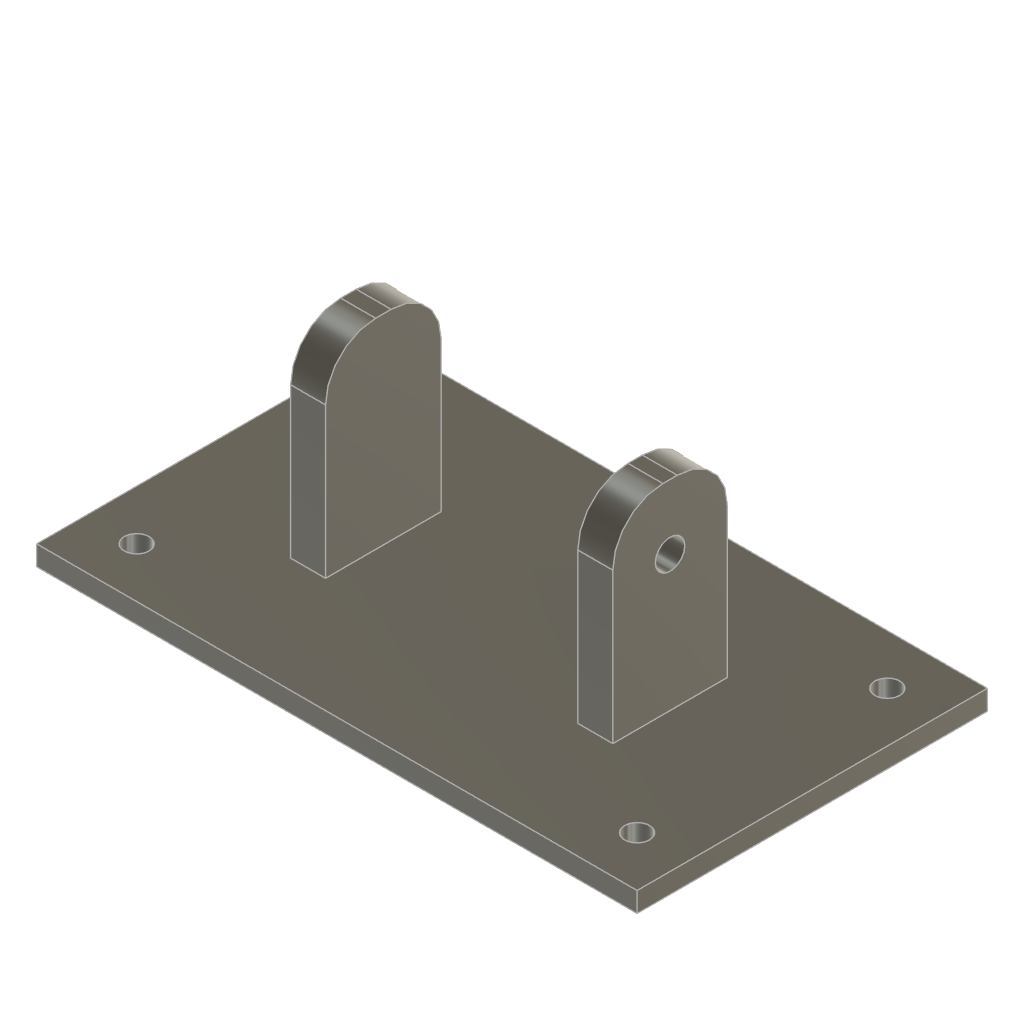
Base (Autodesk Fusion 360 design; units mm, degrees)
part number: 2026-07-20-18-13-44-573
Autodesk Fusion 360 part; units mm, degrees
sketch "Sketch1" plane through (0, 0, 0) normal (0, 0, 1) x (1, 0, 0)
  line L0 (100, -100) -> (-100, -100)
  line L1 (-100, -100) -> (-100, 100)
  line L2 (-100, 100) -> (100, 100)
  line L3 (100, 100) -> (100, -100)
  line L4 (100, -100) -> (-100, 100) construction
  line L5 (-100, -100) -> (100, 100) construction
  dimension "d1" = 200
  dimension "d2" = 200
  constraint horizontal L0
  constraint perpendicular L0 L1
  constraint parallel L0 L2
  constraint parallel L1 L3
  constraint coincident L4 origin
  constraint coincident L5 origin
  measures "d1" distance of L1.end L2.end
  measures "d2" distance of L0.end L1.end
extrude "Extrude1" add sketch "Sketch1" along normal blind 7
sketch "Sketch2" plane through (0, 0, 7) normal (0, 0, 1) x (-1, 0, 0)
  line L0 (-100, -100) -> (100, -100)
  line L1 (100, -100) -> (100, 100)
  line L2 (100, 100) -> (-100, 100)
  line L3 (-100, 100) -> (-100, -100)
  line L4 (0, 0) -> (25.15, 0)
  line L5 (0, 0) -> (-25.15, 0)
  line L6 (25.15, 0) -> (25.15, -10.5)
  line L7 (-25.15, 0) -> (-25.15, -10.5)
  line L8 (-25.15, -10.5) -> (-25.15, 10)
  line L9 (25.15, -10.5) -> (25.15, 11)
  line L10 (25.15, 11) -> (32.15, 11)
  line L11 (32.15, 11) -> (32.15, -10)
  line L12 (32.15, -10) -> (25.15, -10)
  line L13 (25.15, -10) -> (25.15, 11)
  line L14 (-25.15, 10) -> (-32.15, 10)
  line L15 (-32.15, 10) -> (-32.15, -11.3765)
  line L16 (-32.15, -11.3765) -> (-25.15, -11.3765)
  line L17 (-25.15, -11.3765) -> (-25.15, 10)
  dimension "d5" = 25.15
  dimension "d6" = 25.15
  dimension "d7" = 10.5
  dimension "d8" = 10.5
  dimension "d9" = 21.5
  dimension "d10" = 7
  dimension "d11" = 7
  constraint coincident L4.start L5.start
  constraint perpendicular L1 L4
  constraint parallel L4 L5
  constraint perpendicular L4 L6
  constraint perpendicular L5 L7
  constraint perpendicular L5 L8
  constraint perpendicular L4 L9
  constraint horizontal L10
  constraint vertical L11
  constraint horizontal L12
  constraint vertical L13
  constraint horizontal L14
  constraint vertical L15
  constraint horizontal L16
  constraint vertical L17
  measures "d5" distance of L4.start L4.end
  measures "d6" distance of L4.start L5.end
  measures "d7" distance of L4.end L6.end
  measures "d8" distance of L5.end L7.end
  measures "d9" distance of L6.end L9.end
  measures "d10" distance of L9.end L10.end
  measures "d11" distance of L8.end L14.end
extrude "Extrude2" add sketch "Sketch2" along normal blind 30 contours L6 L9 L10 L11 L12 L13 | L7 L8 L14 L15 L16 L17
extrude "Extrude3" add 1 faces at (29.8167, 11.3765, 17) along direction (0, 1, 0) blind 1
extrude "Extrude4" add 1 faces at (-29.8167, 10, 17) along direction (0, 1, 0) blind 1
extrude "Extrude5" add 1 faces at (-27.4833, -11, 17) along direction (0, -1, 0) blind 1
extrude "Extrude6" add 1 faces at (27.4833, -10, 17) along direction (0, -1, 0) blind 1
sketch "Sketch3" plane through (32.15, 0, 0) normal (1, 0, 0) x (0, 1, 0)
  line L0 (-11, 7) -> (12.3765, 7)
  line L1 (12.3765, 7) -> (12.3765, 37)
  line L2 (12.3765, 37) -> (-11, 37)
  line L3 (-11, 37) -> (-11, 7)
  line L4 (0.6883, 37) -> (0.6883, 7)
  line L5 (0.6883, 7) -> (0.6883, 34)
  circle A0 centre (0.7147, 31.0501) radius 2.95
  dimension "d22" = 27
  dimension "d23" = 5.9
  constraint midpoint L2 L4.start
  constraint midpoint L0 L4.end
  constraint perpendicular L0 L5
  constraint coincident L5.end A0
  measures "d22" distance of L4.end L5.end
  measures "d23" diameter of A0
hole "Hole1" at (32.15, 0.7147, 31.0501) direction (-1, 0, 0) diameter 5.9 depth 8 tip angle 180
extrude "Extrude7" add 1 faces at (29.8167, -3.2078, 37) along direction (0, 0, 1) blind 5
extrude "Extrude8" add 1 faces at (-27.4833, -4.3333, 37) along direction (0, 0, 1) blind 5
sketch "Sketch4" plane through (0, 0, 7) normal (0, 0, 1) x (-1, 0, 0)
  line L0 (-25.15, 11) -> (-25.15, -12.3765)
  line L1 (-25.15, -12.3765) -> (-32.15, -12.3765)
  line L2 (-32.15, -12.3765) -> (-32.15, 11)
  line L3 (-32.15, 11) -> (-25.15, 11)
  line L4 (32.15, 12) -> (32.15, -11)
  line L5 (32.15, -11) -> (25.15, -11)
  line L6 (25.15, -11) -> (25.15, 12)
  line L7 (25.15, 12) -> (32.15, 12)
  line L8 (-100, -100) -> (100, -100)
  line L9 (100, -100) -> (100, 100)
  line L10 (100, 100) -> (-100, 100)
  line L11 (-100, 100) -> (-100, -100)
  line L12 (-100, 11) -> (100, 11)
  line L13 (-100, -10) -> (100, -10)
  constraint coincident L11 L12.start
  constraint coincident L9 L12.end
  constraint perpendicular L9 L12
  constraint coincident L11 L13.start
  constraint coincident L9 L13.end
  constraint perpendicular L9 L13
extrude "Extrude9" cut 1 faces at (-27.4833, -12, 30.3333) along direction (0, 1, 0) blind 0.9
extrude "Extrude10" cut 1 faces at (29.8167, 12.3765, 30.3333) along direction (0, -1, 0) blind 2.5
extrude "Extrude11" cut 1 faces at (-29.8167, 11, 30.3333) along direction (0, -1, 0) blind 1
move_face "OffsetFaces1" offset 5 1 faces at (29.8167, 0.8618, 28.1038)
sketch "Sketch5" plane through (32.15, 0, 0) normal (1, 0, 0) x (0, 1, 0)
  line L0 (9.8765, 7) -> (9.8765, 42)
  line L1 (9.8765, 42) -> (-11, 42)
  line L2 (-11, 42) -> (-11, 7)
  line L3 (-11, 7) -> (9.8765, 7)
  line L4 (-0.5617, 7) -> (-0.5617, 34)
  circle A0 centre (-0.5617, 31.05) radius 2.95
  dimension "d38" = 5.9
  constraint midpoint L3 L4.start
  constraint perpendicular L3 L4
  constraint coincident L4.end A0
  measures "d38" diameter of A0
hole "Hole2" at (32.15, -0.5617, 31.05) direction (-1, 0, 0) diameter 5.9 depth 11 tip angle 180
extrude "Extrude12" add 1 faces at (29.8167, 9.8765, 30.3333) along direction (0, 1, 0) blind 1
extrude "Extrude13" add 1 faces at (-29.8167, 10, 30.3333) along direction (0, 1, 0) blind 1
extrude "Extrude14" add 1 faces at (27.4833, -11, 30.3333) along direction (0, -1, 0) blind 1
extrude "Extrude15" add 1 faces at (-27.4833, -11.1, 30.3333) along direction (0, -1, 0) blind 1
extrude "Extrude16" add 2 faces at (29.8167, -4.3745, 42) (-27.4833, -4.4, 42) along direction (0, 0, 1) blind 2
fillet "Fillet1" radius 10 1 edges at (28.65, -12, 44)
fillet "Fillet2" radius 10 1 edges at (28.65, 10.8765, 44)
fillet "Fillet3" radius 10 1 edges at (-28.65, 11, 44)
fillet "Fillet4" radius 10 1 edges at (-28.65, -12.1, 44)
extrude "Extrude17" cut sketch "Sketch4" against normal blind 3 contours L0 L6 L12 L13 | L3 L4 L6 L7 L9 L10 L11 L12 | L0 L1 L2 L4 L5 L6 L8 L9 L11 L13 | L2 L11 L12 L13 | L4 L9 L12 L13
extrude "Extrude18" cut 1 faces at (27.4833, 12.3765, 6) along direction (0, -1, 0) blind 1.5
extrude "Extrude19" add 1 faces at (29.8167, -11, 6) along direction (0, -1, 0) blind 1
extrude "Extrude20" add 1 faces at (-27.4833, -12, 6) along direction (0, -1, 0) blind 0.1
extrude "Extrude21" cut 1 faces at (33.3333, -100, 1.3333) along direction (0, 1, 0) blind 65
extrude "Extrude22" cut 1 faces at (-100, 10, 1.3333) along direction (1, 0, 0) blind 30
extrude "Extrude23" cut 1 faces at (-70, 10, 1.3333) along direction (1, 0, 0) blind 5
extrude "Extrude24" cut 1 faces at (-65, 10, 1.3333) along direction (1, 0, 0) blind 5
extrude "Extrude25" cut 1 faces at (-6.6667, 100, 2.6667) along direction (0, -1, 0) blind 65
extrude "Extrude26" cut 1 faces at (100, 11.6667, 1.3333) along direction (-1, 0, 0) blind 40
sketch "Sketch6" plane through (0, 0, 4) normal (0, 0, 1) x (-1, 0, 0)
  line L0 (-60, 35) -> (-60, -35)
  line L1 (-60, -35) -> (60, -35)
  line L2 (60, -35) -> (60, 35)
  line L3 (60, 35) -> (-60, 35)
  line L4 (25.15, -11) -> (25.15, 12.1)
  line L5 (25.15, 12.1) -> (32.15, 12.1)
  line L6 (32.15, 12.1) -> (32.15, -11)
  line L7 (32.15, -11) -> (25.15, -11)
  line L8 (-25.15, 12) -> (-25.15, -10.8765)
  line L9 (-25.15, -10.8765) -> (-32.15, -10.8765)
  line L10 (-32.15, -10.8765) -> (-32.15, 12)
  line L11 (-32.15, 12) -> (-25.15, 12)
  circle A0 centre (50, -25) radius 2.5
  circle A1 centre (-50, -25) radius 2.5
  circle A2 centre (50, 25) radius 2.5
  circle A3 centre (-50, 25) radius 2.5
  dimension "d80" = 5
  dimension "d81" = 5
  dimension "d82" = 5
  dimension "d83" = 5
  measures "d80" diameter of A0
  measures "d81" diameter of A1
  measures "d82" diameter of A2
  measures "d83" diameter of A3
extrude "Extrude27" cut sketch "Sketch6" against normal blind 5 contours A0 | A1 | A2 | A3
